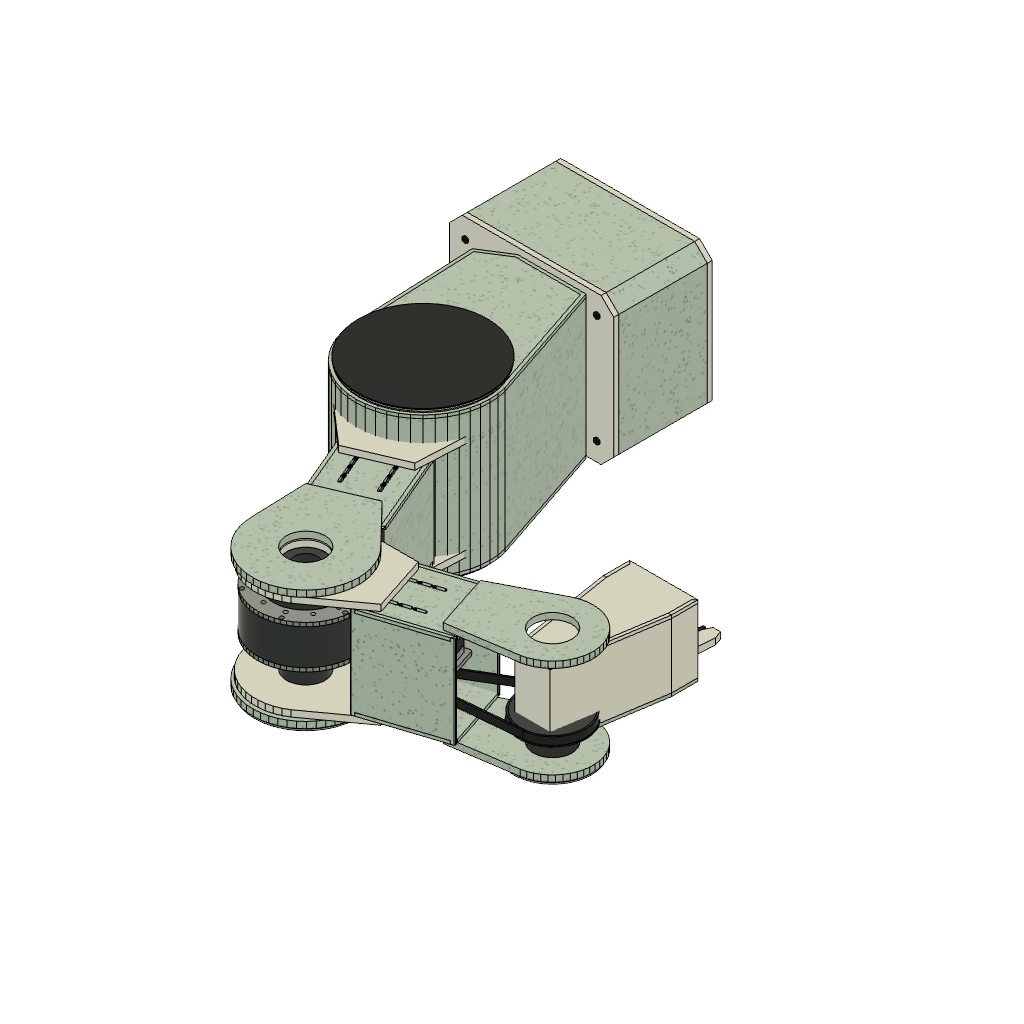
GreenArm-03 (Autodesk Fusion 360 design; units mm, degrees)
part number: 2026-10-22-20-52-36-937
part number: 2026-10-22-20-52-37-335
part number: 2026-10-22-20-52-38-102
part number: 2026-10-22-20-52-40-722
part number: 2026-10-22-20-52-44-928
part number: 2026-10-22-20-52-52-920
part number: 2026-10-22-20-53-04-144
part number: 2026-10-22-20-53-06-303
part number: 2026-10-22-20-53-08-408
part number: 2026-10-22-20-53-10-715
part number: 2026-10-22-20-53-13-054
part number: 2026-10-22-20-53-16-806
part number: 2026-10-22-20-54-16-154
Autodesk Fusion 360 part; units mm, degrees
(part 1 of 8)
sketch "White bench mounting plate | profile" plane through (0, 0, 0) normal (0, 0, 1) x (1, 0, 0) in component "01 | Compact faceted base"
  line L0 (-81, -58) -> (29, -58)
  line L1 (29, -58) -> (39, -48)
  line L2 (39, -48) -> (39, 48)
  line L3 (39, 48) -> (29, 58)
  line L4 (29, 58) -> (-81, 58)
  line L5 (-81, 58) -> (-91, 48)
  line L6 (-91, 48) -> (-91, -48)
  line L7 (-91, -48) -> (-81, -58)
  circle A0 centre (-79, -46) radius 2.75
  circle A1 centre (-79, 46) radius 2.75
  circle A2 centre (27, -46) radius 2.75
  circle A3 centre (27, 46) radius 2.75
extrude "White bench mounting plate" add sketch "White bench mounting plate | profile" along normal blind 4 makes body 1 in component "01 | Compact faceted base"
ref_plane "WorkPlane1" through (0, 0, 4) normal (0, 0, 1) x (1, 0, 0) in component "01 | Compact faceted base"
sketch "Faceted base enclosure | profile" plane through (0, 0, 4) normal (0, 0, 1) x (1, 0, 0) in component "01 | Compact faceted base"
  line L0 (-81, -58) -> (29, -58)
  line L1 (29, -58) -> (39, -48)
  line L2 (39, -48) -> (39, 48)
  line L3 (39, 48) -> (29, 58)
  line L4 (29, 58) -> (-81, 58)
  line L5 (-81, 58) -> (-91, 48)
  line L6 (-91, 48) -> (-91, -48)
  line L7 (-91, -48) -> (-81, -58)
  line L8 (-79.9645, -55.5) -> (27.9645, -55.5)
  line L9 (27.9645, -55.5) -> (36.5, -46.9645)
  line L10 (36.5, -46.9645) -> (36.5, 46.9645)
  line L11 (36.5, 46.9645) -> (27.9645, 55.5)
  line L12 (27.9645, 55.5) -> (-79.9645, 55.5)
  line L13 (-79.9645, 55.5) -> (-88.5, 46.9645)
  line L14 (-88.5, 46.9645) -> (-88.5, -46.9645)
  line L15 (-88.5, -46.9645) -> (-79.9645, -55.5)
extrude "Faceted base enclosure" add sketch "Faceted base enclosure | profile" along normal blind 70 separate body makes body 2 in component "01 | Compact faceted base"
ref_plane "WorkPlane2" through (0, 0, 74) normal (0, 0, 1) x (1, 0, 0) in component "01 | Compact faceted base"
sketch "Flat white base deck | profile" plane through (0, 0, 74) normal (0, 0, 1) x (1, 0, 0) in component "01 | Compact faceted base"
  line L0 (-81, -58) -> (29, -58)
  line L1 (29, -58) -> (39, -48)
  line L2 (39, -48) -> (39, 48)
  line L3 (39, 48) -> (29, 58)
  line L4 (29, 58) -> (-81, 58)
  line L5 (-81, 58) -> (-91, 48)
  line L6 (-91, 48) -> (-91, -48)
  line L7 (-91, -48) -> (-81, -58)
  circle A0 centre (0, 0) radius 10.4
extrude "Flat white base deck" add sketch "Flat white base deck | profile" along normal blind 4 separate body makes body 3 in component "01 | Compact faceted base"
ref_plane "WorkPlane3" through (0, 0, 47) normal (0, 0, 1) x (1, 0, 0) in component "01 | Compact faceted base"
sketch "Motor mount | metal, stock and holes to finalize | profile" plane through (0, 0, 47) normal (0, 0, 1) x (1, 0, 0) in component "01 | Compact faceted base"
  line L0 (-74.65, -23.65) -> (-29.35, -23.65)
  line L1 (-29.35, -23.65) -> (-28.35, -22.65)
  line L2 (-28.35, -22.65) -> (-28.35, 22.65)
  line L3 (-28.35, 22.65) -> (-29.35, 23.65)
  line L4 (-29.35, 23.65) -> (-74.65, 23.65)
  line L5 (-74.65, 23.65) -> (-75.65, 22.65)
  line L6 (-75.65, 22.65) -> (-75.65, -22.65)
  line L7 (-75.65, -22.65) -> (-74.65, -23.65)
  circle A0 centre (-52, 0) radius 11.2
  circle A1 centre (-67.5, -15.5) radius 1.6
  circle A2 centre (-67.5, 15.5) radius 1.6
  circle A3 centre (-36.5, -15.5) radius 1.6
  circle A4 centre (-36.5, 15.5) radius 1.6
extrude "Motor mount | metal, stock and holes to finalize" add sketch "Motor mount | metal, stock and holes to finalize | profile" along normal blind 3 separate body makes body 4 in component "01 | Compact faceted base"
ref_plane "WorkPlane4" through (0, 0, 55) normal (0, 0, 1) x (1, 0, 0) in component "01 | Compact faceted base"
sketch "20T pulley envelope | tooth profile pending | profile" plane through (0, 0, 55) normal (0, 0, 1) x (1, 0, 0) in component "01 | Compact faceted base"
  circle A0 centre (-52, 0) radius 6.9662
  circle A1 centre (-52, 0) radius 2.5
extrude "20T pulley envelope | tooth profile pending" add sketch "20T pulley envelope | tooth profile pending | profile" along normal blind 6 separate body makes body 5 in component "01 | Compact faceted base"
ref_plane "WorkPlane5" through (0, 0, 61) normal (0, 0, 1) x (1, 0, 0) in component "01 | Compact faceted base"
sketch "20T flange | profile" plane through (0, 0, 61) normal (0, 0, 1) x (1, 0, 0) in component "01 | Compact faceted base"
  circle A0 centre (-52, 0) radius 7.3662
  circle A1 centre (-52, 0) radius 2.5
extrude "20T flange" add sketch "20T flange | profile" along normal blind 0.8 separate body makes body 6 in component "01 | Compact faceted base"
ref_plane "WorkPlane6" through (0, 0, 55) normal (0, 0, 1) x (1, 0, 0) in component "01 | Compact faceted base"
sketch "60T pulley envelope | tooth profile pending | profile" plane through (0, 0, 55) normal (0, 0, 1) x (1, 0, 0) in component "01 | Compact faceted base"
  circle A0 centre (0, 0) radius 19.6986
  circle A1 centre (0, 0) radius 10
extrude "60T pulley envelope | tooth profile pending" add sketch "60T pulley envelope | tooth profile pending | profile" along normal blind 6 separate body makes body 7 in component "01 | Compact faceted base"
ref_plane "WorkPlane7" through (0, 0, 61) normal (0, 0, 1) x (1, 0, 0) in component "01 | Compact faceted base"
sketch "60T flange | profile" plane through (0, 0, 61) normal (0, 0, 1) x (1, 0, 0) in component "01 | Compact faceted base"
  circle A0 centre (0, 0) radius 20.0986
  circle A1 centre (0, 0) radius 10
extrude "60T flange" add sketch "60T flange | profile" along normal blind 0.8 separate body makes body 8 in component "01 | Compact faceted base"
ref_plane "WorkPlane8" through (0, 0, 55) normal (0, 0, 1) x (1, 0, 0) in component "01 | Compact faceted base"
sketch "J1 3:1 span | belt length pending | profile" plane through (0, 0, 55) normal (0, 0, 1) x (1, 0, 0) in component "01 | Compact faceted base"
  line L0 (-53.7179, 6.8026) -> (-4.8355, 19.1474)
  line L1 (-4.8355, 19.1474) -> (-4.5172, 17.887)
  line L2 (-4.5172, 17.887) -> (-53.3996, 5.5422)
  line L3 (-53.3996, 5.5422) -> (-53.7179, 6.8026)
extrude "J1 3:1 span | belt length pending" add sketch "J1 3:1 span | belt length pending | profile" along normal blind 6 separate body makes body 9 in component "01 | Compact faceted base"
ref_plane "WorkPlane9" through (0, 0, 55) normal (0, 0, 1) x (1, 0, 0) in component "01 | Compact faceted base"
sketch "J1 3:1 span | belt length pending | profile (1)" plane through (0, 0, 55) normal (0, 0, 1) x (1, 0, 0) in component "01 | Compact faceted base"
  line L0 (-53.3996, -5.5422) -> (-4.5172, -17.887)
  line L1 (-4.5172, -17.887) -> (-4.8355, -19.1474)
  line L2 (-4.8355, -19.1474) -> (-53.7179, -6.8026)
  line L3 (-53.7179, -6.8026) -> (-53.3996, -5.5422)
extrude "J1 3:1 span | belt length pending (1)" add sketch "J1 3:1 span | belt length pending | profile (1)" along normal blind 6 separate body makes body 10 in component "01 | Compact faceted base"
ref_plane "WorkPlane10" through (0, 0, 55) normal (0, 0, 1) x (1, 0, 0) in component "01 | Compact faceted base"
sketch "J1 3:1 drive wrap | profile" plane through (0, 0, 55) normal (0, 0, 1) x (1, 0, 0) in component "01 | Compact faceted base"
  circle A0 centre (-52, 0) radius 7.0162
  circle A1 centre (-52, 0) radius 5.7162
extrude "J1 3:1 drive wrap" add sketch "J1 3:1 drive wrap | profile" along normal blind 6 separate body makes body 11 in component "01 | Compact faceted base"
ref_plane "WorkPlane11" through (0, 0, 55) normal (0, 0, 1) x (1, 0, 0) in component "01 | Compact faceted base"
sketch "J1 3:1 driven wrap | profile" plane through (0, 0, 55) normal (0, 0, 1) x (1, 0, 0) in component "01 | Compact faceted base"
  circle A0 centre (0, 0) radius 19.7486
  circle A1 centre (0, 0) radius 18.4486
extrude "J1 3:1 driven wrap" add sketch "J1 3:1 driven wrap | profile" along normal blind 6 separate body makes body 12 in component "01 | Compact faceted base"
ref_plane "WorkPlane12" through (0, 0, 35) normal (0, 0, 1) x (1, 0, 0) in component "01 | Compact faceted base"
sketch "6004 turntable outer race | profile" plane through (0, 0, 35) normal (0, 0, 1) x (1, 0, 0) in component "01 | Compact faceted base"
  circle A0 centre (0, 0) radius 21
  circle A1 centre (0, 0) radius 20
extrude "6004 turntable outer race" add sketch "6004 turntable outer race | profile" along normal blind 12 separate body makes body 13 in component "01 | Compact faceted base"
ref_plane "WorkPlane13" through (0, 0, 35) normal (0, 0, 1) x (1, 0, 0) in component "01 | Compact faceted base"
sketch "6004 turntable inner race | profile" plane through (0, 0, 35) normal (0, 0, 1) x (1, 0, 0) in component "01 | Compact faceted base"
  circle A0 centre (0, 0) radius 11
  circle A1 centre (0, 0) radius 10
extrude "6004 turntable inner race" add sketch "6004 turntable inner race | profile" along normal blind 12 separate body makes body 14 in component "01 | Compact faceted base"
ref_plane "WorkPlane14" through (0, 0, 35.15) normal (0, 0, 1) x (1, 0, 0) in component "01 | Compact faceted base"
sketch "6004 turntable shield | profile" plane through (0, 0, 35.15) normal (0, 0, 1) x (1, 0, 0) in component "01 | Compact faceted base"
  circle A0 centre (0, 0) radius 20
  circle A1 centre (0, 0) radius 11
extrude "6004 turntable shield" add sketch "6004 turntable shield | profile" along normal blind 11.7 separate body makes body 15 in component "01 | Compact faceted base"
ref_plane "WorkPlane15" through (0, 0, 42) normal (0, 0, 1) x (1, 0, 0) in component "01 | Compact faceted base"
sketch "Yaw output shaft | profile" plane through (0, 0, 42) normal (0, 0, 1) x (1, 0, 0) in component "01 | Compact faceted base"
  circle A0 centre (0, 0) radius 10
  circle A1 centre (0, 0) radius 4
extrude "Yaw output shaft" add sketch "Yaw output shaft | profile" along normal blind 40 separate body makes body 16 in component "01 | Compact faceted base"
ref_plane "WorkPlane16" through (0, 0, -2) normal (0, 0, 1) x (1, 0, 0) in component "01 | Compact faceted base"
sketch "TPU mounting foot | profile" plane through (0, 0, -2) normal (0, 0, 1) x (1, 0, 0) in component "01 | Compact faceted base"
  circle A0 centre (-78, -45) radius 7
extrude "TPU mounting foot" add sketch "TPU mounting foot | profile" along normal blind 2 separate body makes body 17 in component "01 | Compact faceted base"
ref_plane "WorkPlane17" through (0, 0, -2) normal (0, 0, 1) x (1, 0, 0) in component "01 | Compact faceted base"
sketch "TPU mounting foot | profile (1)" plane through (0, 0, -2) normal (0, 0, 1) x (1, 0, 0) in component "01 | Compact faceted base"
  circle A0 centre (-78, 45) radius 7
extrude "TPU mounting foot (1)" add sketch "TPU mounting foot | profile (1)" along normal blind 2 separate body makes body 18 in component "01 | Compact faceted base"
ref_plane "WorkPlane18" through (0, 0, -2) normal (0, 0, 1) x (1, 0, 0) in component "01 | Compact faceted base"
sketch "TPU mounting foot | profile (2)" plane through (0, 0, -2) normal (0, 0, 1) x (1, 0, 0) in component "01 | Compact faceted base"
  circle A0 centre (26, -45) radius 7
extrude "TPU mounting foot (2)" add sketch "TPU mounting foot | profile (2)" along normal blind 2 separate body makes body 19 in component "01 | Compact faceted base"
ref_plane "WorkPlane19" through (0, 0, -2) normal (0, 0, 1) x (1, 0, 0) in component "01 | Compact faceted base"
sketch "TPU mounting foot | profile (3)" plane through (0, 0, -2) normal (0, 0, 1) x (1, 0, 0) in component "01 | Compact faceted base"
  circle A0 centre (26, 45) radius 7
extrude "TPU mounting foot (3)" add sketch "TPU mounting foot | profile (3)" along normal blind 2 separate body makes body 20 in component "01 | Compact faceted base"
ref_plane "WorkPlane20" through (0, 0, 78) normal (0, 0, 1) x (1, 0, 0) in component "01 | Compact faceted base"
sketch "Base service screw | profile" plane through (0, 0, 78) normal (0, 0, 1) x (1, 0, 0) in component "01 | Compact faceted base"
  line L0 (-75.9215, -41.8) -> (-78, -40.6)
  line L1 (-78, -40.6) -> (-80.0785, -41.8)
  line L2 (-80.0785, -41.8) -> (-80.0785, -44.2)
  line L3 (-80.0785, -44.2) -> (-78, -45.4)
  line L4 (-78, -45.4) -> (-75.9215, -44.2)
  line L5 (-75.9215, -44.2) -> (-75.9215, -41.8)
  circle A0 centre (-78, -43) radius 0.9
extrude "Base service screw" add sketch "Base service screw | profile" along normal blind 1 separate body makes body 21 in component "01 | Compact faceted base"
ref_plane "WorkPlane21" through (0, 0, 78) normal (0, 0, 1) x (1, 0, 0) in component "01 | Compact faceted base"
sketch "Base service screw | profile (1)" plane through (0, 0, 78) normal (0, 0, 1) x (1, 0, 0) in component "01 | Compact faceted base"
  line L0 (-75.9215, 44.2) -> (-78, 45.4)
  line L1 (-78, 45.4) -> (-80.0785, 44.2)
  line L2 (-80.0785, 44.2) -> (-80.0785, 41.8)
  line L3 (-80.0785, 41.8) -> (-78, 40.6)
  line L4 (-78, 40.6) -> (-75.9215, 41.8)
  line L5 (-75.9215, 41.8) -> (-75.9215, 44.2)
  circle A0 centre (-78, 43) radius 0.9
extrude "Base service screw (1)" add sketch "Base service screw | profile (1)" along normal blind 1 separate body makes body 22 in component "01 | Compact faceted base"
ref_plane "WorkPlane22" through (0, 0, 78) normal (0, 0, 1) x (1, 0, 0) in component "01 | Compact faceted base"
sketch "Base service screw | profile (2)" plane through (0, 0, 78) normal (0, 0, 1) x (1, 0, 0) in component "01 | Compact faceted base"
  line L0 (28.0785, -41.8) -> (26, -40.6)
  line L1 (26, -40.6) -> (23.9215, -41.8)
  line L2 (23.9215, -41.8) -> (23.9215, -44.2)
  line L3 (23.9215, -44.2) -> (26, -45.4)
  line L4 (26, -45.4) -> (28.0785, -44.2)
  line L5 (28.0785, -44.2) -> (28.0785, -41.8)
  circle A0 centre (26, -43) radius 0.9
extrude "Base service screw (2)" add sketch "Base service screw | profile (2)" along normal blind 1 separate body makes body 23 in component "01 | Compact faceted base"
ref_plane "WorkPlane23" through (0, 0, 78) normal (0, 0, 1) x (1, 0, 0) in component "01 | Compact faceted base"
sketch "Base service screw | profile (3)" plane through (0, 0, 78) normal (0, 0, 1) x (1, 0, 0) in component "01 | Compact faceted base"
  line L0 (28.0785, 44.2) -> (26, 45.4)
  line L1 (26, 45.4) -> (23.9215, 44.2)
  line L2 (23.9215, 44.2) -> (23.9215, 41.8)
  line L3 (23.9215, 41.8) -> (26, 40.6)
  line L4 (26, 40.6) -> (28.0785, 41.8)
  line L5 (28.0785, 41.8) -> (28.0785, 44.2)
  circle A0 centre (26, 43) radius 0.9
extrude "Base service screw (3)" add sketch "Base service screw | profile (3)" along normal blind 1 separate body makes body 24 in component "01 | Compact faceted base"
ref_plane "WorkPlane1" through (0, 0, -55) normal (0, 0, 1) x (1, 0, 0) in component "02 | Flat-sided NEMA23 pedestal"
sketch "Straight-sided torso frame | profile" plane through (0, 0, -55) normal (0, 0, 1) x (1, 0, 0) in component "02 | Flat-sided NEMA23 pedestal"
  line L0 (-110, -19) -> (-13.7174, -51.1941)
  line L1 (-13.7174, -51.1941) -> (-6.9179, -52.5466)
  line L2 (-6.9179, -52.5466) -> (0, -53)
  line L3 (0, -53) -> (6.9179, -52.5466)
  line L4 (6.9179, -52.5466) -> (13.7174, -51.1941)
  line L5 (13.7174, -51.1941) -> (20.2822, -48.9656)
  line L6 (20.2822, -48.9656) -> (26.5, -45.8993)
  line L7 (26.5, -45.8993) -> (32.2644, -42.0477)
  line L8 (32.2644, -42.0477) -> (37.4767, -37.4767)
  line L9 (37.4767, -37.4767) -> (42.0477, -32.2644)
  line L10 (42.0477, -32.2644) -> (45.8993, -26.5)
  line L11 (45.8993, -26.5) -> (48.9656, -20.2822)
  line L12 (48.9656, -20.2822) -> (51.1941, -13.7174)
  line L13 (51.1941, -13.7174) -> (52.5466, -6.9179)
  line L14 (52.5466, -6.9179) -> (53, 0)
  line L15 (53, 0) -> (52.5466, 6.9179)
  line L16 (52.5466, 6.9179) -> (51.1941, 13.7174)
  line L17 (51.1941, 13.7174) -> (48.9656, 20.2822)
  line L18 (48.9656, 20.2822) -> (45.8993, 26.5)
  line L19 (45.8993, 26.5) -> (42.0477, 32.2644)
  line L20 (42.0477, 32.2644) -> (37.4767, 37.4767)
  line L21 (37.4767, 37.4767) -> (32.2644, 42.0477)
  line L22 (32.2644, 42.0477) -> (26.5, 45.8993)
  line L23 (26.5, 45.8993) -> (20.2822, 48.9656)
  line L24 (20.2822, 48.9656) -> (13.7174, 51.1941)
  line L25 (13.7174, 51.1941) -> (6.9179, 52.5466)
  line L26 (6.9179, 52.5466) -> (0, 53)
  line L27 (0, 53) -> (-96, 57)
  line L28 (-96, 57) -> (-110, 35)
  line L29 (-110, 35) -> (-110, -19)
  line L30 (-107.5, -17.1999) -> (-13.0746, -48.773)
  line L31 (-13.0746, -48.773) -> (-6.5909, -50.0626)
  line L32 (-6.5909, -50.0626) -> (0, -50.4946)
  line L33 (0, -50.4946) -> (6.5909, -50.0626)
  line L34 (6.5909, -50.0626) -> (13.069, -48.7741)
  line L35 (13.069, -48.7741) -> (19.3235, -46.651)
  line L36 (19.3235, -46.651) -> (25.2473, -43.7296)
  line L37 (25.2473, -43.7296) -> (30.7392, -40.0601)
  line L38 (30.7392, -40.0601) -> (35.7051, -35.7051)
  line L39 (35.7051, -35.7051) -> (40.0601, -30.7392)
  line L40 (40.0601, -30.7392) -> (43.7296, -25.2473)
  line L41 (43.7296, -25.2473) -> (46.651, -19.3235)
  line L42 (46.651, -19.3235) -> (48.7741, -13.069)
  line L43 (48.7741, -13.069) -> (50.0626, -6.5909)
  line L44 (50.0626, -6.5909) -> (50.4946, 0)
  line L45 (50.4946, 0) -> (50.0626, 6.5909)
  line L46 (50.0626, 6.5909) -> (48.7741, 13.069)
  line L47 (48.7741, 13.069) -> (46.651, 19.3235)
  line L48 (46.651, 19.3235) -> (43.7296, 25.2473)
  line L49 (43.7296, 25.2473) -> (40.0601, 30.7392)
  line L50 (40.0601, 30.7392) -> (35.7051, 35.7051)
  line L51 (35.7051, 35.7051) -> (30.7392, 40.0601)
  line L52 (30.7392, 40.0601) -> (25.2473, 43.7296)
  line L53 (25.2473, 43.7296) -> (19.3235, 46.651)
  line L54 (19.3235, 46.651) -> (13.069, 48.7741)
  line L55 (13.069, 48.7741) -> (6.5909, 50.0626)
  line L56 (6.5909, 50.0626) -> (-0.1338, 50.5034)
  line L57 (-0.1338, 50.5034) -> (-94.6644, 54.4422)
  line L58 (-94.6644, 54.4422) -> (-107.5, 34.272)
  line L59 (-107.5, 34.272) -> (-107.5, -17.1999)
extrude "Straight-sided torso frame" add sketch "Straight-sided torso frame | profile" along normal blind 113 separate body makes body 25 in component "02 | Flat-sided NEMA23 pedestal"
ref_plane "WorkPlane2" through (0, 0, -55) normal (0, 0, 1) x (1, 0, 0) in component "02 | Flat-sided NEMA23 pedestal"
sketch "Flat rear torso panel | profile" plane through (0, 0, -55) normal (0, 0, 1) x (1, 0, 0) in component "02 | Flat-sided NEMA23 pedestal"
  line L0 (-110, -19) -> (-13.7174, -51.1941)
  line L1 (-13.7174, -51.1941) -> (-6.9179, -52.5466)
  line L2 (-6.9179, -52.5466) -> (0, -53)
  line L3 (0, -53) -> (6.9179, -52.5466)
  line L4 (6.9179, -52.5466) -> (13.7174, -51.1941)
  line L5 (13.7174, -51.1941) -> (20.2822, -48.9656)
  line L6 (20.2822, -48.9656) -> (26.5, -45.8993)
  line L7 (26.5, -45.8993) -> (32.2644, -42.0477)
  line L8 (32.2644, -42.0477) -> (37.4767, -37.4767)
  line L9 (37.4767, -37.4767) -> (42.0477, -32.2644)
  line L10 (42.0477, -32.2644) -> (45.8993, -26.5)
  line L11 (45.8993, -26.5) -> (48.9656, -20.2822)
  line L12 (48.9656, -20.2822) -> (51.1941, -13.7174)
  line L13 (51.1941, -13.7174) -> (52.5466, -6.9179)
  line L14 (52.5466, -6.9179) -> (53, 0)
  line L15 (53, 0) -> (52.5466, 6.9179)
  line L16 (52.5466, 6.9179) -> (51.1941, 13.7174)
  line L17 (51.1941, 13.7174) -> (48.9656, 20.2822)
  line L18 (48.9656, 20.2822) -> (45.8993, 26.5)
  line L19 (45.8993, 26.5) -> (42.0477, 32.2644)
  line L20 (42.0477, 32.2644) -> (37.4767, 37.4767)
  line L21 (37.4767, 37.4767) -> (32.2644, 42.0477)
  line L22 (32.2644, 42.0477) -> (26.5, 45.8993)
  line L23 (26.5, 45.8993) -> (20.2822, 48.9656)
  line L24 (20.2822, 48.9656) -> (13.7174, 51.1941)
  line L25 (13.7174, 51.1941) -> (6.9179, 52.5466)
  line L26 (6.9179, 52.5466) -> (0, 53)
  line L27 (0, 53) -> (-96, 57)
  line L28 (-96, 57) -> (-110, 35)
  line L29 (-110, 35) -> (-110, -19)
  circle A0 centre (0, 0) radius 50.5
extrude "Flat rear torso panel" add sketch "Flat rear torso panel | profile" along normal blind 2.5 separate body makes body 26 in component "02 | Flat-sided NEMA23 pedestal"
ref_plane "WorkPlane3" through (0, 0, 55.5) normal (0, 0, 1) x (1, 0, 0) in component "02 | Flat-sided NEMA23 pedestal"
sketch "Flat front torso panel | profile" plane through (0, 0, 55.5) normal (0, 0, 1) x (1, 0, 0) in component "02 | Flat-sided NEMA23 pedestal"
  line L0 (-110, -19) -> (-13.7174, -51.1941)
  line L1 (-13.7174, -51.1941) -> (-6.9179, -52.5466)
  line L2 (-6.9179, -52.5466) -> (0, -53)
  line L3 (0, -53) -> (6.9179, -52.5466)
  line L4 (6.9179, -52.5466) -> (13.7174, -51.1941)
  line L5 (13.7174, -51.1941) -> (20.2822, -48.9656)
  line L6 (20.2822, -48.9656) -> (26.5, -45.8993)
  line L7 (26.5, -45.8993) -> (32.2644, -42.0477)
  line L8 (32.2644, -42.0477) -> (37.4767, -37.4767)
  line L9 (37.4767, -37.4767) -> (42.0477, -32.2644)
  line L10 (42.0477, -32.2644) -> (45.8993, -26.5)
  line L11 (45.8993, -26.5) -> (48.9656, -20.2822)
  line L12 (48.9656, -20.2822) -> (51.1941, -13.7174)
  line L13 (51.1941, -13.7174) -> (52.5466, -6.9179)
  line L14 (52.5466, -6.9179) -> (53, 0)
  line L15 (53, 0) -> (52.5466, 6.9179)
  line L16 (52.5466, 6.9179) -> (51.1941, 13.7174)
  line L17 (51.1941, 13.7174) -> (48.9656, 20.2822)
  line L18 (48.9656, 20.2822) -> (45.8993, 26.5)
  line L19 (45.8993, 26.5) -> (42.0477, 32.2644)
  line L20 (42.0477, 32.2644) -> (37.4767, 37.4767)
  line L21 (37.4767, 37.4767) -> (32.2644, 42.0477)
  line L22 (32.2644, 42.0477) -> (26.5, 45.8993)
  line L23 (26.5, 45.8993) -> (20.2822, 48.9656)
  line L24 (20.2822, 48.9656) -> (13.7174, 51.1941)
  line L25 (13.7174, 51.1941) -> (6.9179, 52.5466)
  line L26 (6.9179, 52.5466) -> (0, 53)
  line L27 (0, 53) -> (-96, 57)
  line L28 (-96, 57) -> (-110, 35)
  line L29 (-110, 35) -> (-110, -19)
  circle A0 centre (0, 0) radius 50.5
extrude "Flat front torso panel" add sketch "Flat front torso panel | profile" along normal blind 2.5 separate body makes body 27 in component "02 | Flat-sided NEMA23 pedestal"
ref_plane "WorkPlane4" through (0, 0, 31.5) normal (0, 0, 1) x (1, 0, 0) in component "02 | Flat-sided NEMA23 pedestal"
sketch "Motor mount | metal, stock and holes to finalize | profile (2)" plane through (0, 0, 31.5) normal (0, 0, 1) x (1, 0, 0) in component "02 | Flat-sided NEMA23 pedestal"
  line L0 (-92, -11) -> (-32, -11)
  line L1 (-32, -11) -> (-31, -10)
  line L2 (-31, -10) -> (-31, 50)
  line L3 (-31, 50) -> (-32, 51)
  line L4 (-32, 51) -> (-92, 51)
  line L5 (-92, 51) -> (-93, 50)
  line L6 (-93, 50) -> (-93, -10)
  line L7 (-93, -10) -> (-92, -11)
  circle A0 centre (-62, 20) radius 19.3
  circle A1 centre (-85.57, -3.57) radius 2.7
  circle A2 centre (-85.57, 43.57) radius 2.7
  circle A3 centre (-38.43, -3.57) radius 2.7
  circle A4 centre (-38.43, 43.57) radius 2.7
extrude "Motor mount | metal, stock and holes to finalize'" add sketch "Motor mount | metal, stock and holes to finalize | profile (2)" along normal blind 3 separate body makes body 28 in component "02 | Flat-sided NEMA23 pedestal"
ref_plane "WorkPlane5" through (0, 0, 43) normal (0, 0, 1) x (1, 0, 0) in component "02 | Flat-sided NEMA23 pedestal"
sketch "20T pulley envelope | tooth profile pending | profile (2)" plane through (0, 0, 43) normal (0, 0, 1) x (1, 0, 0) in component "02 | Flat-sided NEMA23 pedestal"
  circle A0 centre (-62, 20) radius 6.9662
  circle A1 centre (-62, 20) radius 3.175
extrude "20T pulley envelope | tooth profile pending'" add sketch "20T pulley envelope | tooth profile pending | profile (2)" along normal blind 6 separate body makes body 29 in component "02 | Flat-sided NEMA23 pedestal"
ref_plane "WorkPlane6" through (0, 0, 49) normal (0, 0, 1) x (1, 0, 0) in component "02 | Flat-sided NEMA23 pedestal"
sketch "20T flange | profile (2)" plane through (0, 0, 49) normal (0, 0, 1) x (1, 0, 0) in component "02 | Flat-sided NEMA23 pedestal"
  circle A0 centre (-62, 20) radius 7.3662
  circle A1 centre (-62, 20) radius 3.175
extrude "20T flange'" add sketch "20T flange | profile (2)" along normal blind 0.8 separate body makes body 30 in component "02 | Flat-sided NEMA23 pedestal"
ref_plane "WorkPlane7" through (0, 0, 43) normal (0, 0, 1) x (1, 0, 0) in component "02 | Flat-sided NEMA23 pedestal"
sketch "20T pulley envelope | tooth profile pending | profile (1)" plane through (0, 0, 43) normal (0, 0, 1) x (1, 0, 0) in component "02 | Flat-sided NEMA23 pedestal"
  circle A0 centre (0, 0) radius 6.9662
  circle A1 centre (0, 0) radius 3
extrude "20T pulley envelope | tooth profile pending (1)" add sketch "20T pulley envelope | tooth profile pending | profile (1)" along normal blind 6 separate body makes body 31 in component "02 | Flat-sided NEMA23 pedestal"
ref_plane "WorkPlane8" through (0, 0, 49) normal (0, 0, 1) x (1, 0, 0) in component "02 | Flat-sided NEMA23 pedestal"
sketch "20T flange | profile (1)" plane through (0, 0, 49) normal (0, 0, 1) x (1, 0, 0) in component "02 | Flat-sided NEMA23 pedestal"
  circle A0 centre (0, 0) radius 7.3662
  circle A1 centre (0, 0) radius 3
extrude "20T flange (1)" add sketch "20T flange | profile (1)" along normal blind 0.8 separate body makes body 32 in component "02 | Flat-sided NEMA23 pedestal"
ref_plane "WorkPlane9" through (0, 0, 43) normal (0, 0, 1) x (1, 0, 0) in component "02 | Flat-sided NEMA23 pedestal"
sketch "J2 1:1 enclosed span | belt length pending | profile" plane through (0, 0, 43) normal (0, 0, 1) x (1, 0, 0) in component "02 | Flat-sided NEMA23 pedestal"
  line L0 (-59.846, 26.6774) -> (2.154, 6.6774)
  line L1 (2.154, 6.6774) -> (1.7549, 5.4402)
  line L2 (1.7549, 5.4402) -> (-60.2451, 25.4402)
  line L3 (-60.2451, 25.4402) -> (-59.846, 26.6774)
extrude "J2 1:1 enclosed span | belt length pending" add sketch "J2 1:1 enclosed span | belt length pending | profile" along normal blind 6 separate body makes body 33 in component "02 | Flat-sided NEMA23 pedestal"
ref_plane "WorkPlane10" through (0, 0, 43) normal (0, 0, 1) x (1, 0, 0) in component "02 | Flat-sided NEMA23 pedestal"
sketch "J2 1:1 enclosed span | belt length pending | profile (1)" plane through (0, 0, 43) normal (0, 0, 1) x (1, 0, 0) in component "02 | Flat-sided NEMA23 pedestal"
  line L0 (-63.7549, 14.5598) -> (-1.7549, -5.4402)
  line L1 (-1.7549, -5.4402) -> (-2.154, -6.6774)
  line L2 (-2.154, -6.6774) -> (-64.154, 13.3226)
  line L3 (-64.154, 13.3226) -> (-63.7549, 14.5598)
extrude "J2 1:1 enclosed span | belt length pending (1)" add sketch "J2 1:1 enclosed span | belt length pending | profile (1)" along normal blind 6 separate body makes body 34 in component "02 | Flat-sided NEMA23 pedestal"
ref_plane "WorkPlane11" through (0, 0, 43) normal (0, 0, 1) x (1, 0, 0) in component "02 | Flat-sided NEMA23 pedestal"
sketch "J2 1:1 enclosed drive wrap | profile" plane through (0, 0, 43) normal (0, 0, 1) x (1, 0, 0) in component "02 | Flat-sided NEMA23 pedestal"
  circle A0 centre (-62, 20) radius 7.0162
  circle A1 centre (-62, 20) radius 5.7162
extrude "J2 1:1 enclosed drive wrap" add sketch "J2 1:1 enclosed drive wrap | profile" along normal blind 6 separate body makes body 35 in component "02 | Flat-sided NEMA23 pedestal"
ref_plane "WorkPlane12" through (0, 0, 43) normal (0, 0, 1) x (1, 0, 0) in component "02 | Flat-sided NEMA23 pedestal"
sketch "J2 1:1 enclosed driven wrap | profile" plane through (0, 0, 43) normal (0, 0, 1) x (1, 0, 0) in component "02 | Flat-sided NEMA23 pedestal"
  circle A0 centre (0, 0) radius 7.0162
  circle A1 centre (0, 0) radius 5.7162
extrude "J2 1:1 enclosed driven wrap" add sketch "J2 1:1 enclosed driven wrap | profile" along normal blind 6 separate body makes body 36 in component "02 | Flat-sided NEMA23 pedestal"
ref_plane "WorkPlane13" through (0, 0, 58.4) normal (0, 0, 1) x (1, 0, 0) in component "02 | Flat-sided NEMA23 pedestal"
sketch "Shoulder front recessed graphite seam | profile" plane through (0, 0, 58.4) normal (0, 0, 1) x (1, 0, 0) in component "02 | Flat-sided NEMA23 pedestal"
  circle A0 centre (0, 0) radius 51
extrude "Shoulder front recessed graphite seam" add sketch "Shoulder front recessed graphite seam | profile" along normal blind 0.7 separate body makes body 37 in component "02 | Flat-sided NEMA23 pedestal"
ref_plane "WorkPlane14" through (0, 0, 59.1) normal (0, 0, 1) x (1, 0, 0) in component "02 | Flat-sided NEMA23 pedestal"
sketch "Shoulder front narrow white annulus | profile" plane through (0, 0, 59.1) normal (0, 0, 1) x (1, 0, 0) in component "02 | Flat-sided NEMA23 pedestal"
  circle A0 centre (0, 0) radius 50.7
  circle A1 centre (0, 0) radius 49.3
extrude "Shoulder front narrow white annulus" add sketch "Shoulder front narrow white annulus | profile" along normal blind 1.3 separate body makes body 38 in component "02 | Flat-sided NEMA23 pedestal"
ref_plane "WorkPlane15" through (0, 0, 59.1) normal (0, 0, 1) x (1, 0, 0) in component "02 | Flat-sided NEMA23 pedestal"
sketch "Shoulder front flat Green Marble face | profile" plane through (0, 0, 59.1) normal (0, 0, 1) x (1, 0, 0) in component "02 | Flat-sided NEMA23 pedestal"
  line L0 (49, 0) -> (48.7641, 4.8028)
  line L1 (48.7641, 4.8028) -> (48.0585, 9.5594)
  line L2 (48.0585, 9.5594) -> (46.8901, 14.2239)
  line L3 (46.8901, 14.2239) -> (45.2701, 18.7515)
  line L4 (45.2701, 18.7515) -> (43.2141, 23.0984)
  line L5 (43.2141, 23.0984) -> (40.742, 27.2229)
  line L6 (40.742, 27.2229) -> (37.8775, 31.0853)
  line L7 (37.8775, 31.0853) -> (34.6482, 34.6482)
  line L8 (34.6482, 34.6482) -> (31.0853, 37.8775)
  line L9 (31.0853, 37.8775) -> (27.2229, 40.742)
  line L10 (27.2229, 40.742) -> (23.0984, 43.2141)
  line L11 (23.0984, 43.2141) -> (18.7515, 45.2701)
  line L12 (18.7515, 45.2701) -> (14.2239, 46.8901)
  line L13 (14.2239, 46.8901) -> (9.5594, 48.0585)
  line L14 (9.5594, 48.0585) -> (4.8028, 48.7641)
  line L15 (4.8028, 48.7641) -> (0, 49)
  line L16 (0, 49) -> (-4.8028, 48.7641)
  line L17 (-4.8028, 48.7641) -> (-9.5594, 48.0585)
  line L18 (-9.5594, 48.0585) -> (-14.2239, 46.8901)
  line L19 (-14.2239, 46.8901) -> (-18.7515, 45.2701)
  line L20 (-18.7515, 45.2701) -> (-23.0984, 43.2141)
  line L21 (-23.0984, 43.2141) -> (-27.2229, 40.742)
  line L22 (-27.2229, 40.742) -> (-31.0853, 37.8775)
  line L23 (-31.0853, 37.8775) -> (-34.6482, 34.6482)
  line L24 (-34.6482, 34.6482) -> (-37.8775, 31.0853)
  line L25 (-37.8775, 31.0853) -> (-40.742, 27.2229)
  line L26 (-40.742, 27.2229) -> (-43.2141, 23.0984)
  line L27 (-43.2141, 23.0984) -> (-45.2701, 18.7515)
  line L28 (-45.2701, 18.7515) -> (-46.8901, 14.2239)
  line L29 (-46.8901, 14.2239) -> (-48.0585, 9.5594)
  line L30 (-48.0585, 9.5594) -> (-48.7641, 4.8028)
  line L31 (-48.7641, 4.8028) -> (-49, 0)
  line L32 (-49, 0) -> (-48.7641, -4.8028)
  line L33 (-48.7641, -4.8028) -> (-48.0585, -9.5594)
  line L34 (-48.0585, -9.5594) -> (-46.8901, -14.2239)
  line L35 (-46.8901, -14.2239) -> (-45.2701, -18.7515)
  line L36 (-45.2701, -18.7515) -> (-43.2141, -23.0984)
  line L37 (-43.2141, -23.0984) -> (-40.742, -27.2229)
  line L38 (-40.742, -27.2229) -> (-37.8775, -31.0853)
  line L39 (-37.8775, -31.0853) -> (-34.6482, -34.6482)
  line L40 (-34.6482, -34.6482) -> (-31.0853, -37.8775)
  line L41 (-31.0853, -37.8775) -> (-27.2229, -40.742)
  line L42 (-27.2229, -40.742) -> (-23.0984, -43.2141)
  line L43 (-23.0984, -43.2141) -> (-18.7515, -45.2701)
  line L44 (-18.7515, -45.2701) -> (-14.2239, -46.8901)
  line L45 (-14.2239, -46.8901) -> (-9.5594, -48.0585)
  line L46 (-9.5594, -48.0585) -> (-4.8028, -48.7641)
  line L47 (-4.8028, -48.7641) -> (0, -49)
  line L48 (0, -49) -> (4.8028, -48.7641)
  line L49 (4.8028, -48.7641) -> (9.5594, -48.0585)
  line L50 (9.5594, -48.0585) -> (14.2239, -46.8901)
  line L51 (14.2239, -46.8901) -> (18.7515, -45.2701)
  line L52 (18.7515, -45.2701) -> (23.0984, -43.2141)
  line L53 (23.0984, -43.2141) -> (27.2229, -40.742)
  line L54 (27.2229, -40.742) -> (31.0853, -37.8775)
  line L55 (31.0853, -37.8775) -> (34.6482, -34.6482)
  line L56 (34.6482, -34.6482) -> (37.8775, -31.0853)
  line L57 (37.8775, -31.0853) -> (40.742, -27.2229)
  line L58 (40.742, -27.2229) -> (43.2141, -23.0984)
  line L59 (43.2141, -23.0984) -> (45.2701, -18.7515)
  line L60 (45.2701, -18.7515) -> (46.8901, -14.2239)
  line L61 (46.8901, -14.2239) -> (48.0585, -9.5594)
  line L62 (48.0585, -9.5594) -> (48.7641, -4.8028)
  line L63 (48.7641, -4.8028) -> (49, 0)
  circle A0 centre (44, 0) radius 1.65
  circle A1 centre (22, 38.1051) radius 1.65
  circle A2 centre (-22, 38.1051) radius 1.65
  circle A3 centre (-44, 0) radius 1.65
  circle A4 centre (-22, -38.1051) radius 1.65
  circle A5 centre (22, -38.1051) radius 1.65
extrude "Shoulder front flat Green Marble face" add sketch "Shoulder front flat Green Marble face | profile" along normal blind 1.4 separate body makes body 39 in component "02 | Flat-sided NEMA23 pedestal"
ref_plane "WorkPlane16" through (0, 0, 60.55) normal (0, 0, 1) x (1, 0, 0) in component "02 | Flat-sided NEMA23 pedestal"
sketch "Shoulder front flush M3 head | profile" plane through (0, 0, 60.55) normal (0, 0, 1) x (1, 0, 0) in component "02 | Flat-sided NEMA23 pedestal"
  line L0 (45.9486, 1.125) -> (44, 2.25)
  line L1 (44, 2.25) -> (42.0514, 1.125)
  line L2 (42.0514, 1.125) -> (42.0514, -1.125)
  line L3 (42.0514, -1.125) -> (44, -2.25)
  line L4 (44, -2.25) -> (45.9486, -1.125)
  line L5 (45.9486, -1.125) -> (45.9486, 1.125)
  circle A0 centre (44, 0) radius 0.9
extrude "Shoulder front flush M3 head" add sketch "Shoulder front flush M3 head | profile" along normal blind 0.6 separate body makes body 40 in component "02 | Flat-sided NEMA23 pedestal"
ref_plane "WorkPlane17" through (0, 0, 60.55) normal (0, 0, 1) x (1, 0, 0) in component "02 | Flat-sided NEMA23 pedestal"
sketch "Shoulder front flush M3 head | profile (1)" plane through (0, 0, 60.55) normal (0, 0, 1) x (1, 0, 0) in component "02 | Flat-sided NEMA23 pedestal"
  line L0 (23.9486, 39.2301) -> (22, 40.3551)
  line L1 (22, 40.3551) -> (20.0514, 39.2301)
  line L2 (20.0514, 39.2301) -> (20.0514, 36.9801)
  line L3 (20.0514, 36.9801) -> (22, 35.8551)
  line L4 (22, 35.8551) -> (23.9486, 36.9801)
  line L5 (23.9486, 36.9801) -> (23.9486, 39.2301)
  circle A0 centre (22, 38.1051) radius 0.9
extrude "Shoulder front flush M3 head (1)" add sketch "Shoulder front flush M3 head | profile (1)" along normal blind 0.6 separate body makes body 41 in component "02 | Flat-sided NEMA23 pedestal"
ref_plane "WorkPlane18" through (0, 0, 60.55) normal (0, 0, 1) x (1, 0, 0) in component "02 | Flat-sided NEMA23 pedestal"
sketch "Shoulder front flush M3 head | profile (2)" plane through (0, 0, 60.55) normal (0, 0, 1) x (1, 0, 0) in component "02 | Flat-sided NEMA23 pedestal"
  line L0 (-20.0514, 39.2301) -> (-22, 40.3551)
  line L1 (-22, 40.3551) -> (-23.9486, 39.2301)
  line L2 (-23.9486, 39.2301) -> (-23.9486, 36.9801)
  line L3 (-23.9486, 36.9801) -> (-22, 35.8551)
  line L4 (-22, 35.8551) -> (-20.0514, 36.9801)
  line L5 (-20.0514, 36.9801) -> (-20.0514, 39.2301)
  circle A0 centre (-22, 38.1051) radius 0.9
extrude "Shoulder front flush M3 head (2)" add sketch "Shoulder front flush M3 head | profile (2)" along normal blind 0.6 separate body makes body 42 in component "02 | Flat-sided NEMA23 pedestal"
ref_plane "WorkPlane19" through (0, 0, 60.55) normal (0, 0, 1) x (1, 0, 0) in component "02 | Flat-sided NEMA23 pedestal"
sketch "Shoulder front flush M3 head | profile (3)" plane through (0, 0, 60.55) normal (0, 0, 1) x (1, 0, 0) in component "02 | Flat-sided NEMA23 pedestal"
  line L0 (-42.0514, 1.125) -> (-44, 2.25)
  line L1 (-44, 2.25) -> (-45.9486, 1.125)
  line L2 (-45.9486, 1.125) -> (-45.9486, -1.125)
  line L3 (-45.9486, -1.125) -> (-44, -2.25)
  line L4 (-44, -2.25) -> (-42.0514, -1.125)
  line L5 (-42.0514, -1.125) -> (-42.0514, 1.125)
  circle A0 centre (-44, 0) radius 0.9
extrude "Shoulder front flush M3 head (3)" add sketch "Shoulder front flush M3 head | profile (3)" along normal blind 0.6 separate body makes body 43 in component "02 | Flat-sided NEMA23 pedestal"
ref_plane "WorkPlane20" through (0, 0, 60.55) normal (0, 0, 1) x (1, 0, 0) in component "02 | Flat-sided NEMA23 pedestal"
sketch "Shoulder front flush M3 head | profile (4)" plane through (0, 0, 60.55) normal (0, 0, 1) x (1, 0, 0) in component "02 | Flat-sided NEMA23 pedestal"
  line L0 (-20.0514, -36.9801) -> (-22, -35.8551)
  line L1 (-22, -35.8551) -> (-23.9486, -36.9801)
  line L2 (-23.9486, -36.9801) -> (-23.9486, -39.2301)
  line L3 (-23.9486, -39.2301) -> (-22, -40.3551)
  line L4 (-22, -40.3551) -> (-20.0514, -39.2301)
  line L5 (-20.0514, -39.2301) -> (-20.0514, -36.9801)
  circle A0 centre (-22, -38.1051) radius 0.9
extrude "Shoulder front flush M3 head (4)" add sketch "Shoulder front flush M3 head | profile (4)" along normal blind 0.6 separate body makes body 44 in component "02 | Flat-sided NEMA23 pedestal"
ref_plane "WorkPlane21" through (0, 0, 60.55) normal (0, 0, 1) x (1, 0, 0) in component "02 | Flat-sided NEMA23 pedestal"
sketch "Shoulder front flush M3 head | profile (5)" plane through (0, 0, 60.55) normal (0, 0, 1) x (1, 0, 0) in component "02 | Flat-sided NEMA23 pedestal"
  line L0 (23.9486, -36.9801) -> (22, -35.8551)
  line L1 (22, -35.8551) -> (20.0514, -36.9801)
  line L2 (20.0514, -36.9801) -> (20.0514, -39.2301)
  line L3 (20.0514, -39.2301) -> (22, -40.3551)
  line L4 (22, -40.3551) -> (23.9486, -39.2301)
  line L5 (23.9486, -39.2301) -> (23.9486, -36.9801)
  circle A0 centre (22, -38.1051) radius 0.9
extrude "Shoulder front flush M3 head (5)" add sketch "Shoulder front flush M3 head | profile (5)" along normal blind 0.6 separate body makes body 45 in component "02 | Flat-sided NEMA23 pedestal"
ref_plane "WorkPlane22" through (0, 0, -58) normal (0, 0, 1) x (1, 0, 0) in component "02 | Flat-sided NEMA23 pedestal"
sketch "Shoulder rear recessed graphite seam | profile" plane through (0, 0, -58) normal (0, 0, 1) x (1, 0, 0) in component "02 | Flat-sided NEMA23 pedestal"
  circle A0 centre (0, 0) radius 51
extrude "Shoulder rear recessed graphite seam" add sketch "Shoulder rear recessed graphite seam | profile" along normal blind 0.7 separate body makes body 46 in component "02 | Flat-sided NEMA23 pedestal"
ref_plane "WorkPlane23" through (0, 0, -57.3) normal (0, 0, 1) x (1, 0, 0) in component "02 | Flat-sided NEMA23 pedestal"
sketch "Shoulder rear narrow white annulus | profile" plane through (0, 0, -57.3) normal (0, 0, 1) x (1, 0, 0) in component "02 | Flat-sided NEMA23 pedestal"
  circle A0 centre (0, 0) radius 50.7
  circle A1 centre (0, 0) radius 49.3
extrude "Shoulder rear narrow white annulus" add sketch "Shoulder rear narrow white annulus | profile" along normal blind 1.3 separate body makes body 47 in component "02 | Flat-sided NEMA23 pedestal"
ref_plane "WorkPlane24" through (0, 0, -57.3) normal (0, 0, 1) x (1, 0, 0) in component "02 | Flat-sided NEMA23 pedestal"
sketch "Shoulder rear flat Green Marble face | profile" plane through (0, 0, -57.3) normal (0, 0, 1) x (1, 0, 0) in component "02 | Flat-sided NEMA23 pedestal"
  line L0 (49, 0) -> (48.7641, 4.8028)
  line L1 (48.7641, 4.8028) -> (48.0585, 9.5594)
  line L2 (48.0585, 9.5594) -> (46.8901, 14.2239)
  line L3 (46.8901, 14.2239) -> (45.2701, 18.7515)
  line L4 (45.2701, 18.7515) -> (43.2141, 23.0984)
  line L5 (43.2141, 23.0984) -> (40.742, 27.2229)
  line L6 (40.742, 27.2229) -> (37.8775, 31.0853)
  line L7 (37.8775, 31.0853) -> (34.6482, 34.6482)
  line L8 (34.6482, 34.6482) -> (31.0853, 37.8775)
  line L9 (31.0853, 37.8775) -> (27.2229, 40.742)
  line L10 (27.2229, 40.742) -> (23.0984, 43.2141)
  line L11 (23.0984, 43.2141) -> (18.7515, 45.2701)
  line L12 (18.7515, 45.2701) -> (14.2239, 46.8901)
  line L13 (14.2239, 46.8901) -> (9.5594, 48.0585)
  line L14 (9.5594, 48.0585) -> (4.8028, 48.7641)
  line L15 (4.8028, 48.7641) -> (0, 49)
  line L16 (0, 49) -> (-4.8028, 48.7641)
  line L17 (-4.8028, 48.7641) -> (-9.5594, 48.0585)
  line L18 (-9.5594, 48.0585) -> (-14.2239, 46.8901)
  line L19 (-14.2239, 46.8901) -> (-18.7515, 45.2701)
  line L20 (-18.7515, 45.2701) -> (-23.0984, 43.2141)
  line L21 (-23.0984, 43.2141) -> (-27.2229, 40.742)
  line L22 (-27.2229, 40.742) -> (-31.0853, 37.8775)
  line L23 (-31.0853, 37.8775) -> (-34.6482, 34.6482)
  line L24 (-34.6482, 34.6482) -> (-37.8775, 31.0853)
  line L25 (-37.8775, 31.0853) -> (-40.742, 27.2229)
  line L26 (-40.742, 27.2229) -> (-43.2141, 23.0984)
  line L27 (-43.2141, 23.0984) -> (-45.2701, 18.7515)
  line L28 (-45.2701, 18.7515) -> (-46.8901, 14.2239)
  line L29 (-46.8901, 14.2239) -> (-48.0585, 9.5594)
  line L30 (-48.0585, 9.5594) -> (-48.7641, 4.8028)
  line L31 (-48.7641, 4.8028) -> (-49, 0)
  line L32 (-49, 0) -> (-48.7641, -4.8028)
  line L33 (-48.7641, -4.8028) -> (-48.0585, -9.5594)
  line L34 (-48.0585, -9.5594) -> (-46.8901, -14.2239)
  line L35 (-46.8901, -14.2239) -> (-45.2701, -18.7515)
  line L36 (-45.2701, -18.7515) -> (-43.2141, -23.0984)
  line L37 (-43.2141, -23.0984) -> (-40.742, -27.2229)
  line L38 (-40.742, -27.2229) -> (-37.8775, -31.0853)
  line L39 (-37.8775, -31.0853) -> (-34.6482, -34.6482)
  line L40 (-34.6482, -34.6482) -> (-31.0853, -37.8775)
  line L41 (-31.0853, -37.8775) -> (-27.2229, -40.742)
  line L42 (-27.2229, -40.742) -> (-23.0984, -43.2141)
  line L43 (-23.0984, -43.2141) -> (-18.7515, -45.2701)
  line L44 (-18.7515, -45.2701) -> (-14.2239, -46.8901)
  line L45 (-14.2239, -46.8901) -> (-9.5594, -48.0585)
  line L46 (-9.5594, -48.0585) -> (-4.8028, -48.7641)
  line L47 (-4.8028, -48.7641) -> (0, -49)
  line L48 (0, -49) -> (4.8028, -48.7641)
  line L49 (4.8028, -48.7641) -> (9.5594, -48.0585)
  line L50 (9.5594, -48.0585) -> (14.2239, -46.8901)
  line L51 (14.2239, -46.8901) -> (18.7515, -45.2701)
  line L52 (18.7515, -45.2701) -> (23.0984, -43.2141)
  line L53 (23.0984, -43.2141) -> (27.2229, -40.742)
  line L54 (27.2229, -40.742) -> (31.0853, -37.8775)
  line L55 (31.0853, -37.8775) -> (34.6482, -34.6482)
  line L56 (34.6482, -34.6482) -> (37.8775, -31.0853)
  line L57 (37.8775, -31.0853) -> (40.742, -27.2229)
  line L58 (40.742, -27.2229) -> (43.2141, -23.0984)
  line L59 (43.2141, -23.0984) -> (45.2701, -18.7515)
  line L60 (45.2701, -18.7515) -> (46.8901, -14.2239)
  line L61 (46.8901, -14.2239) -> (48.0585, -9.5594)
  line L62 (48.0585, -9.5594) -> (48.7641, -4.8028)
  line L63 (48.7641, -4.8028) -> (49, 0)
  circle A0 centre (44, 0) radius 1.65
  circle A1 centre (22, 38.1051) radius 1.65
  circle A2 centre (-22, 38.1051) radius 1.65
  circle A3 centre (-44, 0) radius 1.65
  circle A4 centre (-22, -38.1051) radius 1.65
  circle A5 centre (22, -38.1051) radius 1.65
extrude "Shoulder rear flat Green Marble face" add sketch "Shoulder rear flat Green Marble face | profile" along normal blind 1.4 separate body makes body 48 in component "02 | Flat-sided NEMA23 pedestal"
ref_plane "WorkPlane25" through (0, 0, -55.85) normal (0, 0, 1) x (1, 0, 0) in component "02 | Flat-sided NEMA23 pedestal"
sketch "Shoulder rear flush M3 head | profile" plane through (0, 0, -55.85) normal (0, 0, 1) x (1, 0, 0) in component "02 | Flat-sided NEMA23 pedestal"
  line L0 (45.9486, 1.125) -> (44, 2.25)
  line L1 (44, 2.25) -> (42.0514, 1.125)
  line L2 (42.0514, 1.125) -> (42.0514, -1.125)
  line L3 (42.0514, -1.125) -> (44, -2.25)
  line L4 (44, -2.25) -> (45.9486, -1.125)
  line L5 (45.9486, -1.125) -> (45.9486, 1.125)
  circle A0 centre (44, 0) radius 0.9
extrude "Shoulder rear flush M3 head" add sketch "Shoulder rear flush M3 head | profile" along normal blind 0.6 separate body makes body 49 in component "02 | Flat-sided NEMA23 pedestal"
ref_plane "WorkPlane26" through (0, 0, -55.85) normal (0, 0, 1) x (1, 0, 0) in component "02 | Flat-sided NEMA23 pedestal"
sketch "Shoulder rear flush M3 head | profile (1)" plane through (0, 0, -55.85) normal (0, 0, 1) x (1, 0, 0) in component "02 | Flat-sided NEMA23 pedestal"
  line L0 (23.9486, 39.2301) -> (22, 40.3551)
  line L1 (22, 40.3551) -> (20.0514, 39.2301)
  line L2 (20.0514, 39.2301) -> (20.0514, 36.9801)
  line L3 (20.0514, 36.9801) -> (22, 35.8551)
  line L4 (22, 35.8551) -> (23.9486, 36.9801)
  line L5 (23.9486, 36.9801) -> (23.9486, 39.2301)
  circle A0 centre (22, 38.1051) radius 0.9
extrude "Shoulder rear flush M3 head (1)" add sketch "Shoulder rear flush M3 head | profile (1)" along normal blind 0.6 separate body makes body 50 in component "02 | Flat-sided NEMA23 pedestal"
ref_plane "WorkPlane27" through (0, 0, -55.85) normal (0, 0, 1) x (1, 0, 0) in component "02 | Flat-sided NEMA23 pedestal"
sketch "Shoulder rear flush M3 head | profile (2)" plane through (0, 0, -55.85) normal (0, 0, 1) x (1, 0, 0) in component "02 | Flat-sided NEMA23 pedestal"
  line L0 (-20.0514, 39.2301) -> (-22, 40.3551)
  line L1 (-22, 40.3551) -> (-23.9486, 39.2301)
  line L2 (-23.9486, 39.2301) -> (-23.9486, 36.9801)
  line L3 (-23.9486, 36.9801) -> (-22, 35.8551)
  line L4 (-22, 35.8551) -> (-20.0514, 36.9801)
  line L5 (-20.0514, 36.9801) -> (-20.0514, 39.2301)
  circle A0 centre (-22, 38.1051) radius 0.9
extrude "Shoulder rear flush M3 head (2)" add sketch "Shoulder rear flush M3 head | profile (2)" along normal blind 0.6 separate body makes body 51 in component "02 | Flat-sided NEMA23 pedestal"
ref_plane "WorkPlane28" through (0, 0, -55.85) normal (0, 0, 1) x (1, 0, 0) in component "02 | Flat-sided NEMA23 pedestal"
sketch "Shoulder rear flush M3 head | profile (3)" plane through (0, 0, -55.85) normal (0, 0, 1) x (1, 0, 0) in component "02 | Flat-sided NEMA23 pedestal"
  line L0 (-42.0514, 1.125) -> (-44, 2.25)
  line L1 (-44, 2.25) -> (-45.9486, 1.125)
  line L2 (-45.9486, 1.125) -> (-45.9486, -1.125)
  line L3 (-45.9486, -1.125) -> (-44, -2.25)
  line L4 (-44, -2.25) -> (-42.0514, -1.125)
  line L5 (-42.0514, -1.125) -> (-42.0514, 1.125)
  circle A0 centre (-44, 0) radius 0.9
extrude "Shoulder rear flush M3 head (3)" add sketch "Shoulder rear flush M3 head | profile (3)" along normal blind 0.6 separate body makes body 52 in component "02 | Flat-sided NEMA23 pedestal"
ref_plane "WorkPlane29" through (0, 0, -55.85) normal (0, 0, 1) x (1, 0, 0) in component "02 | Flat-sided NEMA23 pedestal"
sketch "Shoulder rear flush M3 head | profile (4)" plane through (0, 0, -55.85) normal (0, 0, 1) x (1, 0, 0) in component "02 | Flat-sided NEMA23 pedestal"
  line L0 (-20.0514, -36.9801) -> (-22, -35.8551)
  line L1 (-22, -35.8551) -> (-23.9486, -36.9801)
  line L2 (-23.9486, -36.9801) -> (-23.9486, -39.2301)
  line L3 (-23.9486, -39.2301) -> (-22, -40.3551)
  line L4 (-22, -40.3551) -> (-20.0514, -39.2301)
  line L5 (-20.0514, -39.2301) -> (-20.0514, -36.9801)
  circle A0 centre (-22, -38.1051) radius 0.9
extrude "Shoulder rear flush M3 head (4)" add sketch "Shoulder rear flush M3 head | profile (4)" along normal blind 0.6 separate body makes body 53 in component "02 | Flat-sided NEMA23 pedestal"
ref_plane "WorkPlane30" through (0, 0, -55.85) normal (0, 0, 1) x (1, 0, 0) in component "02 | Flat-sided NEMA23 pedestal"
sketch "Shoulder rear flush M3 head | profile (5)" plane through (0, 0, -55.85) normal (0, 0, 1) x (1, 0, 0) in component "02 | Flat-sided NEMA23 pedestal"
  line L0 (23.9486, -36.9801) -> (22, -35.8551)
  line L1 (22, -35.8551) -> (20.0514, -36.9801)
  line L2 (20.0514, -36.9801) -> (20.0514, -39.2301)
  line L3 (20.0514, -39.2301) -> (22, -40.3551)
  line L4 (22, -40.3551) -> (23.9486, -39.2301)
  line L5 (23.9486, -39.2301) -> (23.9486, -36.9801)
  circle A0 centre (22, -38.1051) radius 0.9
extrude "Shoulder rear flush M3 head (5)" add sketch "Shoulder rear flush M3 head | profile (5)" along normal blind 0.6 separate body makes body 54 in component "02 | Flat-sided NEMA23 pedestal"
ref_plane "WorkPlane31" through (0, 0, 58.15) normal (0, 0, 1) x (1, 0, 0) in component "02 | Flat-sided NEMA23 pedestal"
sketch "Narrow white torso service rail | profile" plane through (0, 0, 58.15) normal (0, 0, 1) x (1, 0, 0) in component "02 | Flat-sided NEMA23 pedestal"
  line L0 (-98.9, -20.5) -> (-37.1, -20.5)
  line L1 (-37.1, -20.5) -> (-36.5, -19.9)
  line L2 (-36.5, -19.9) -> (-36.5, -18.1)
  line L3 (-36.5, -18.1) -> (-37.1, -17.5)
  line L4 (-37.1, -17.5) -> (-98.9, -17.5)
  line L5 (-98.9, -17.5) -> (-99.5, -18.1)
  line L6 (-99.5, -18.1) -> (-99.5, -19.9)
  line L7 (-99.5, -19.9) -> (-98.9, -20.5)
extrude "Narrow white torso service rail" add sketch "Narrow white torso service rail | profile" along normal blind 1.1 separate body makes body 55 in component "02 | Flat-sided NEMA23 pedestal"
ref_plane "WorkPlane32" through (0, 0, 58) normal (0, 0, 1) x (1, 0, 0) in component "02 | Flat-sided NEMA23 pedestal"
sketch "Torso panel screw | profile" plane through (0, 0, 58) normal (0, 0, 1) x (1, 0, 0) in component "02 | Flat-sided NEMA23 pedestal"
  line L0 (-97.0947, 19.1) -> (-99, 20.2)
  line L1 (-99, 20.2) -> (-100.9053, 19.1)
  line L2 (-100.9053, 19.1) -> (-100.9053, 16.9)
  line L3 (-100.9053, 16.9) -> (-99, 15.8)
  line L4 (-99, 15.8) -> (-97.0947, 16.9)
  line L5 (-97.0947, 16.9) -> (-97.0947, 19.1)
  circle A0 centre (-99, 18) radius 0.9
extrude "Torso panel screw" add sketch "Torso panel screw | profile" along normal blind 1 separate body makes body 56 in component "02 | Flat-sided NEMA23 pedestal"
ref_plane "WorkPlane33" through (0, 0, 58) normal (0, 0, 1) x (1, 0, 0) in component "02 | Flat-sided NEMA23 pedestal"